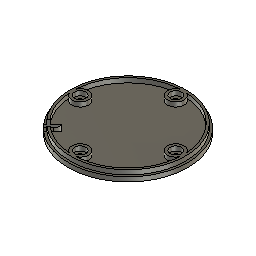
LAMP TOP COVER (Autodesk Fusion 360 design; units mm, degrees)
part number: 2026-05-20-23-41-38-894
Autodesk Fusion 360 part; units mm, degrees
sketch "Sketch1" plane through (0, 0, 0) normal (0, 0, 1) x (1, 0, 0)
  circle A0 centre (0, 0) radius 40
  circle A1 centre (0, 0) radius 38.5
  dimension "d1" = 80
  dimension "d2" = 77
  constraint coincident A0.centre A1.centre
  constraint concentric A0 A1
  measures "d1" diameter of A0
  measures "d2" diameter of A1
extrude "Extrude1" add sketch "Sketch1" along normal blind 3 contours A0 | A1
sketch "Sketch2" plane through (0, 0, 3) normal (0, 0, 1) x (-1, 0, 0)
  circle A0 centre (0, 0) radius 40
  circle A1 centre (0, 0) radius 38.5
  circle A2 centre (0, 0) radius 37
  dimension "d5" = 77
  dimension "d6" = 74
  constraint coincident A0.centre A1.centre
  constraint concentric A1 A2
  measures "d5" diameter of A1
  measures "d6" diameter of A2
extrude "Extrude2" add sketch "Sketch2" along normal blind 3 contours A1
sketch "Sketch3" plane through (0, 0, 3) normal (0, 0, 1) x (-1, 0, 0)
  circle A0 centre (0, 0) radius 37
  circle A1 centre (-32, 0) radius 5.5
  circle A2 centre (-32, 0) radius 3.75
  circle A3 centre (0, -32) radius 5.5
  circle A4 centre (0, -32) radius 3.75
  circle A5 centre (32, 0) radius 5.5
  circle A6 centre (32, 0) radius 3.75
  circle A7 centre (0, 32) radius 5.5
  circle A8 centre (0, 32) radius 3.75
  dimension "d9" = 11
  dimension "d10" = 7.5
  dimension "d11" = 32
  dimension "d13" = 360
  constraint concentric A1 A2
  measures "d9" diameter of A1
  measures "d10" diameter of A2
  measures "d11" distance of A0.centre A1.centre
extrude "Extrude3" add sketch "Sketch3" along normal blind 3 contours A0 A5 | A0 A7 | A0 A3 | A0 A1 picked at (36.1717, -2.5797) picked at (-1.5513, 36.4665) picked at (1.5513, -36.4665) picked at (-36.4974, 1.463)
sketch "Sketch4" plane through (0, 0, 3) normal (0, 0, 1) x (-1, 0, 0)
  circle A0 centre (32, 0) radius 3.75
  circle A1 centre (32, 0) radius 1.6
  circle A2 centre (0, 32) radius 1.6
  circle A3 centre (-32, 0) radius 1.6
  circle A4 centre (0, -32) radius 1.6
  dimension "d16" = 3.2
  dimension "d17" = 32
  dimension "d19" = 360
  constraint concentric A0 A1
  measures "d16" diameter of A1
  measures "d17" distance of origin A0.centre
extrude "Extrude4" cut sketch "Sketch4" against normal through all draft 25.02 contours A1 | A2 | A3 | A4
ref_plane "WorkPlane1" through (0, 0, 0) normal (-0.707107, 0.707107, 0) x (0, 0, 1)
sketch "Sketch5" plane through (0, 0, 0) normal (-0.707107, 0.707107, 0) x (0, 0, 1)
  line L0 (3, -40) -> (3, 40)
  line L1 (6, -38.5) -> (6, 38.5)
  line L2 (3, 38.5) -> (3, -38.5)
  line L3 (3, -40) -> (3, 40)
  line L4 (0, -40) -> (0, 40)
  line L5 (6, -38.5) -> (3, -38.5)
  line L6 (3, -38.5) -> (3, -36.5)
  line L7 (3, -36.5) -> (6, -36.5)
  line L8 (6, -36.5) -> (6, -38.5)
  line L9 (6, -40) -> (1, -40)
  line L10 (6, -40) -> (6, -30.653)
  line L11 (1, -40) -> (1, -35.115)
  arc A0 (6, -30.653) -> (1, -35.115) centre (5.491, -35.1151) ccw
  dimension "d21" = 2
  dimension "d22" = 3
  dimension "d23" = 5
  dimension "d24" = 3
  dimension "d25" = 9.347
  dimension "d26" = 4.885
  dimension "d27" = 4.491
  constraint horizontal L5
  constraint vertical L6
  constraint horizontal L7
  constraint vertical L8
  constraint coincident L1.start L5.start
  constraint horizontal L9
  constraint perpendicular L9 L10
  constraint perpendicular L9 L11
  constraint coincident L11.end A0.end
  measures "d21" distance of L1.start L7.end
  measures "d22" distance of L6.end L7.end
  measures "d23" distance of L9.start L9.end
  measures "d24" distance of L0 L9.start
  measures "d25" distance of L9.start L10.end
  measures "d26" distance of L9.end L11.end
  measures "d27" radius of A0
extrude "Extrude5" cut sketch "Sketch5" along normal mid plane 6
